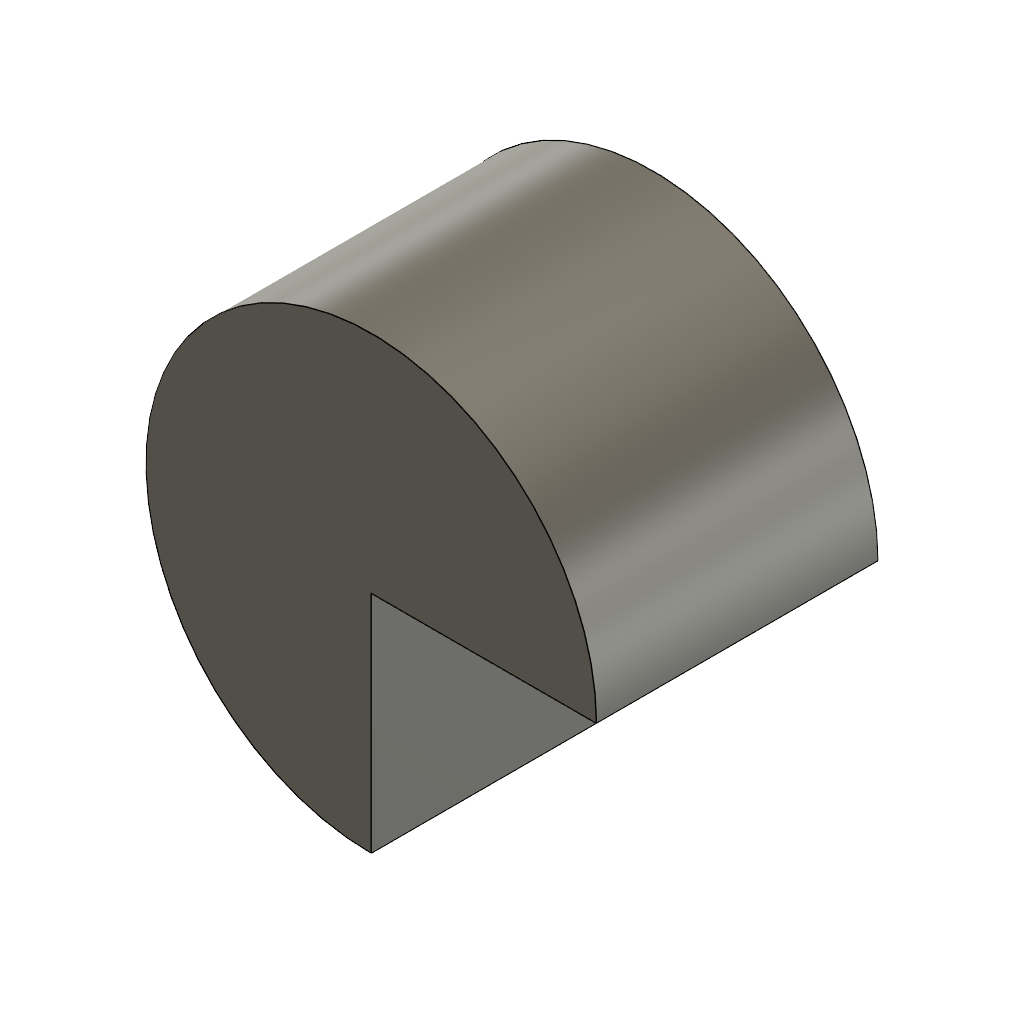
rev_about_profile_edge (Autodesk Fusion 360 design; units mm, degrees)
part number: 2026-11-13-14-38-04-844
Autodesk Fusion 360 part; units mm, degrees
sketch "Sketch1" plane through (0, 0, 0) normal (0, 1, 0) x (1, 0, 0)
  line L0 (0, 0) -> (12, 0)
  line L1 (12, 0) -> (12, 15)
  line L2 (12, 15) -> (0, 10)
  line L3 (0, 10) -> (0, 0)
revolve "Revolve1" add sketch "Sketch1" angle 270 about axis through (0, 0, -10) along (0, 0, 1)
